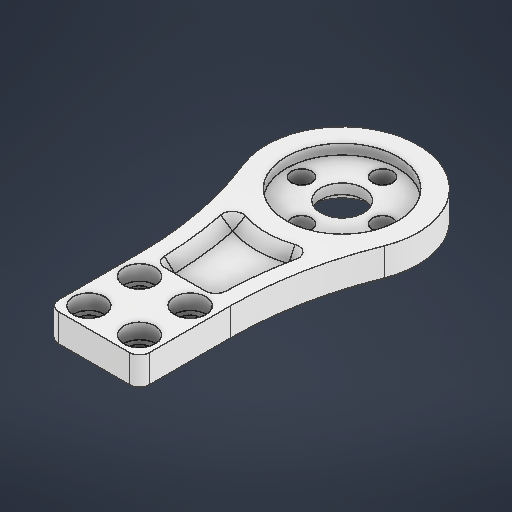
# Autodesk Inventor part: Flange Bracket
Saved by Autodesk Inventor 2026.2 (Build 302298010, 298A)
## iProperties
Created: 2026-05-08
Part Number: Flange Bracket
Material: ABS 플라스틱
Document SubType Name: Modeling
Designer: work
Density: 1.06 g/cm^3
Appearance: 매끄러움 - 흰색
Author: work
Autodesk Inventor part; units mm, degrees
ref_plane "YZ Plane" through (0, 0, 0) normal (1, 0, 0) x (0, 1, 0)
ref_plane "XZ Plane" through (0, 0, 0) normal (0, 1, 0) x (-1, 0, 0)
ref_plane "XY Plane" through (0, 0, 0) normal (0, 0, 1) x (1, 0, 0)
sketch "스케치1" plane through (0, 0, 0) normal (0, 1, 0) x (-1, 0, 0)
  line L0 (-5, 5) -> (5, 5) construction
  line L1 (5, 5) -> (5, -5) construction
  line L2 (5, -5) -> (-5, -5) construction
  line L3 (-5, -5) -> (-5, 5) construction
  line L4 (-5, 5) -> (5, -5) construction
  line L5 (5, 5) -> (-5, -5) construction
  circle A0 centre (5, 5) radius 2
  circle A1 centre (5, -5) radius 2
  circle A2 centre (-5, -5) radius 2
  circle A3 centre (-5, 5) radius 2
  line L6 (-9, 9) -> (9, 9)
  line L7 (9, 9) -> (9, -9)
  line L8 (9, -9) -> (-9, -9)
  line L9 (-9, -9) -> (-9, 9)
  line L10 (-9, 9) -> (9, -9) construction
  line L11 (9, 9) -> (-9, -9) construction
  circle A4 centre (0, -40) radius 11
  line L12 (0, -40) -> (8, -40) construction
  circle A5 centre (0, -40) radius 4.25
  line L13 (0, -40) -> (0, 0) construction
  circle A6 centre (8, -40) radius 2
  line L14 (0, -40) -> (0, -32) construction
  circle A7 centre (0, -32) radius 2
  line L15 (0, -40) -> (-8, -40) construction
  circle A8 centre (-8, -40) radius 2
  line L16 (0, -40) -> (0, -48) construction
  circle A9 centre (0, -48) radius 2
  circle A10 centre (0, -40) radius 15
  arc A11 (9, -9) -> (13.9168, -34.4032) centre (77.0833, -9) ccw
  arc A12 (-13.9168, -34.4032) -> (-9, -9) centre (-77.0833, -9) ccw
  arc A13 (6, -9) -> (8.4849, -27.6304) centre (77.0833, -9) ccw
  line L17 (6, -9) -> (6, 9) construction
  arc A14 (-8.4849, -27.6304) -> (-6, -9) centre (-77.0833, -9) ccw
  point P0 (-13.9168, -34.4032)
  point P1 (-8.4849, -27.6304)
  point P2 (-6, -9)
  dimension "d0" = 10
  dimension "d1" = 10
  dimension "d2" = 4
  dimension "d3" = 4
  dimension "d4" = 4
  dimension "d5" = 4
  dimension "d6" = 18
  dimension "d7" = 18
  dimension "d8" = 22
  dimension "d9" = 8
  dimension "d10" = 8.5
  dimension "d11" = 40
  dimension "d12" = 4
  dimension "d15" = 360
  dimension "d17" = 30
  dimension "d18" = 3
  constraints: 36 end point, 15 centre point, 10 coincident, 10 point on circle, 5 symmetric about line, 4 midpoint, 4 parallel, 3 horizontal, 3 perpendicular, 3 tangent, 2 point on line, 1 concentric, 1 vertical, 23 other
  measures "d0" distance of L1.end L2.end
  measures "d1" distance of L0.end L1.end
  measures "d2" diameter of A0
  measures "d3" diameter of A1
  measures "d4" diameter of A2
  measures "d5" diameter of A3
  measures "d6" distance of L7.end L8.end
  measures "d7" distance of L6.end L7.end
  measures "d8" diameter of A4
  measures "d9" distance of L12.start L12.end
  measures "d10" diameter of A5
  measures "d11" distance of L13.start L13.end
  measures "d12" diameter of A6
  measures "d17" diameter of A10
  measures "d18" distance between parallel lines of L7 L17
extrude "돌출1" add sketch "스케치1" along normal blind 6 contours L6 L7 L8 L9 | L8 A14 A10 A12 | A11 A10 A13 L8 | A10
extrude "돌출2" add sketch "스케치1" along normal blind 4 contours L8 A13 A10 A14 | A4
fillet "모깎기1" radius 2 6 edges at (8.4849, 5, -27.6304) (-8.4849, 5, -27.6304) (-6, 5, -9) (6, 5, -9) (-9, 3, 9) (9, 3, 9)
chamfer "모따기1" distance 2 angle 45 9 edges at (6.4822, 4, -17.2654) (5.4221, 4, -9.5666) (0, 4, -9) (-5.4221, 4, -9.5666) (-6.4822, 4, -17.2654) (-6.8631, 4, -25.429) (0, 4, -25) (6.8631, 4, -25.429) (4.25, 0, -40)
sketch "스케치2" plane through (0, 6, 0) normal (0, 1, 0) x (1, 0, 0)
  circle A0 centre (5, 5) radius 2 projected
  circle A1 centre (5, -5) radius 2 projected
  circle A2 centre (-5, 5) radius 2 projected
  circle A3 centre (-5, -5) radius 2 projected
  point P0 (0, 0)
  constraints: 4 coincident
hole "구멍1" at (5, 6, -5) at (5, 6, 5) at (-5, 6, -5) at (-5, 6, 5) direction (0, -1, 0) diameter 4 end through all counterbore diameter 6.2 counterbore depth 3
chamfer "모따기2" distance 0.5 angle 45 8 edges at (0, 0, -55) (-10.2405, 0, -21.9373) (-9, 0, -1) (-8.4142, 0, 8.4142) (0, 0, 9) (8.4142, 0, 8.4142) (9, 0, -1) (10.2405, 0, -21.9373)
